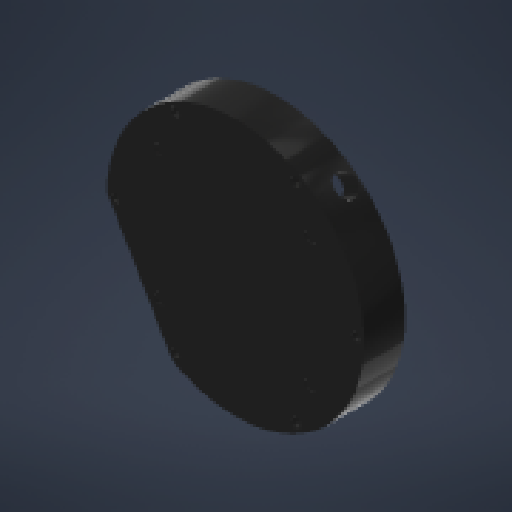
# Autodesk Inventor part: cover for electrical box
Saved by Autodesk Inventor 2027.1 (Build 311270010, 270A)
## iProperties
Created: 2026-10-20
Part Number: cover for electrical box
Material: Printed PLA Plastic
Document SubType Name: Modeling
Designer: youss
Density: 1.14 g/cm^3
Appearance: Smooth - Black
Author: youss
Autodesk Inventor part; units mm, degrees
ref_plane "XY Plane" through (0, 0, 0) normal (0, 0, 1) x (1, 0, 0)
sketch "Sketch1" plane through (0, 0, 0) normal (0, 0, 1) x (1, 0, 0)
  line L0 (-106.0871, 0) -> (113.3016, 0) projected
  line L1 (0, -109.7468) -> (0, 113.9116) projected
  circle A0 centre (0, 33) radius 2
  circle A1 centre (0, 0) radius 30
  circle A2 centre (28.5788, 16.5) radius 2
  circle A3 centre (28.5788, -16.5) radius 2
  circle A4 centre (0, -33) radius 2
  circle A5 centre (-28.5788, -16.5) radius 2
  circle A6 centre (-28.5788, 16.5) radius 2
  line L2 (-59.9972, 0.5821) -> (-29.4999, -52.2471)
  arc A7 (-29.4999, -52.2471) -> (-59.9972, 0.5821) centre (0, 0) ccw
  circle A8 centre (28, 48.4974) radius 2
  circle A9 centre (28, -48.4974) radius 2
  circle A10 centre (-28, 48.4974) radius 2
  circle A11 centre (56, 0) radius 2
  circle A12 centre (-52.9217, -3.6738) radius 2
  circle A13 centre (-32.5754, -38.9188) radius 2
  line L3 (-23.7061, -46.282) -> (-51.9341, 2.6162)
  arc A14 (-23.7061, -46.282) -> (-51.9341, 2.6162) centre (0, 0) ccw
  point P0 (0, 0)
  dimension "d5" = 8
  constraints: 15 centre point, 4 end point, 4 point on circle, 2 point on line, 1 other
  measures "d5" radial gap between concentric circles of A7 A14
extrude "Extrusion1" add sketch "Sketch1" along normal blind 17 contours L2 A7 L1 A14 L3 L0 | L0 L3 A14 L1 A7 L2 | A7 L0 A11 A14 L1 | L1 A14 L0 A11 A7
sketch "Sketch2" plane through (0, 0, 17) normal (0, 0, 1) x (1, 0, 0)
  line L0 (-59.9399, -2.6852) -> (-38.825, -45.7452) projected
  arc A0 (-38.825, -45.7452) -> (-59.9399, -2.6852) centre (0, 0) ccw projected
  circle A1 centre (-28, -48.4974) radius 2 projected
  circle A2 centre (-28, 48.4974) radius 2 projected
  circle A3 centre (-56, 0) radius 2 projected
  arc A4 (-32.404, -40.6692) -> (-51.9951, -0.7168) centre (0, 0) ccw projected
  line L1 (-32.404, -40.6692) -> (-51.9951, -0.7168) projected
  circle A5 centre (28, -48.4974) radius 2 projected
  circle A6 centre (28, 48.4974) radius 2 projected
  circle A7 centre (56, 0) radius 2 projected
extrude "Extrusion2" add sketch "Sketch2" along normal blind 2 contours A0 L0 | L1 A4
move faces "Move1" translate (0, 0, 26.75) faces at (-40.747, -34.3441, 17)
sketch "Sketch4" plane through (0, 0, 19) normal (0, 0, 1) x (1, 0, 0)
  line L0 (35, 30) -> (-35, 30)
  line L1 (-35, 30) -> (-35, -30)
  line L2 (-35, -30) -> (35, -30)
  line L3 (35, -30) -> (35, 30)
  line L4 (35, 30) -> (-35, -30)
  line L5 (35, -30) -> (-35, 30)
  arc A0 (-23.7061, -46.282) -> (-51.9341, 2.6162) centre (0, 0) ccw projected
  line L6 (-29.4999, -52.2471) -> (-59.9972, 0.5821) projected
  arc A1 (-29.4999, -52.2471) -> (-59.9972, 0.5821) centre (0, 0) ccw projected
  circle A2 centre (56, 0) radius 2 projected
  circle A3 centre (28, 48.4974) radius 2 projected
  circle A4 centre (28, -48.4974) radius 2 projected
  circle A5 centre (-56, 0) radius 2 projected
  circle A6 centre (-28, 48.4974) radius 2 projected
  circle A7 centre (-28, -48.4974) radius 2 projected
  circle A8 centre (35, 30) radius 2.5
  circle A9 centre (35, -30) radius 2.5
  circle A10 centre (-35, -30) radius 2.5
  circle A11 centre (-35, 30) radius 2.5
  dimension "d10" = 60
  dimension "d11" = 70
  dimension "d12" = 5
  dimension "d13" = 5
  dimension "d14" = 5
  dimension "d15" = 5
  constraints: 12 end point, 5 coincident, 4 centre point, 2 parallel, 1 horizontal, 1 midpoint, 1 perpendicular
  measures "d10" distance of L2.end L0.start
  measures "d11" distance of L1.end L2.end
  measures "d12" diameter of A8
  measures "d13" diameter of A9
  measures "d14" diameter of A10
  measures "d15" diameter of A11
extrude "Extrusion3" cut sketch "Sketch4" against normal blind 0.5 contours A11 L5 L0 | L0 L1 A11 | L5 A11 L1 | A8 L3 L0 | L0 L4 A8 | L3 A8 L4 | A10 L4 L1 | L1 L2 A10 | L4 A10 L2 | A9 L3 L5 | L5 L2 A9 | A9 L2 L3
sketch "Sketch5" plane through (-59.9972, 0.5821, 0) normal (-0.8660512, -0.4999554, 0) x (0, 0, 1)
  point P0 (0, -30.5)
sketch "Sketch6" plane through (-59.9972, 0.5821, 0) normal (-0.8660512, -0.4999554, 0) x (0, 0, 1)
  line L0 (0, -61) -> (19, -61) projected
  line L1 (0, 0) -> (0, -61) projected
  line L2 (0.56, -31.9394) -> (0.56, -25.5994)
  arc A0 (0.56, -31.9394) -> (1.86, -33.2394) centre (1.86, -31.9394) ccw
  arc A1 (1.86, -24.2994) -> (0.56, -25.5994) centre (1.86, -25.5994) ccw
  line L3 (2.42, -33.2394) -> (1.86, -33.2394)
  arc A2 (2.42, -33.2394) -> (3.72, -31.9394) centre (2.42, -31.9394) ccw
  line L4 (3.72, -25.5994) -> (3.72, -31.9394)
  arc A3 (3.72, -25.5994) -> (2.42, -24.2994) centre (2.42, -25.5994) ccw
  line L5 (1.86, -24.2994) -> (2.42, -24.2994)
  point P0 (0, -30.5)
  point P1 (2.14, -33.2394)
  point P2 (2.14, -33.2394)
  dimension "d18" = 27.7605
  dimension "d19" = 2.14
  constraints: 8 end point, 8 point on circle, 4 centre point, 1 midpoint
  measures "d18" distance from line of L0 point (2.14, -33.239)
  measures "d19" distance from line of L1 point (2.14, -33.239)
extrude "Extrusion4" cut sketch "Sketch6" against normal blind 61.63
chamfer "Chamfer1" distance 2 angle 45 8 edges at (-45.6137, -24.3338, 3.72) (-43.5693, -27.8753, 3.3392) (-43.3789, -28.205, 2.14) (-43.5693, -27.8753, 0.9408) (-45.6137, -24.3338, 0.56) (-47.6582, -20.7923, 0.9408) (-47.8485, -20.4625, 2.14) (-47.6582, -20.7923, 3.3392)
ref_plane "Work Plane1" through (-60, 0, 0) normal (1, 0, 0) x (0, 1, 0)
ref_plane "Work Plane2" through (0, 60, 0) normal (0, 1, 0) x (-1, 0, 0)
sketch "Sketch7" plane through (0, 60, 0) normal (0, 1, 0) x (-1, 0, 0)
  circle A0 centre (-7.2183, 7.2874) radius 4.95
  point P0 (0, 0)
  dimension "d25" = 9.9
  constraints: 1 centre point
  measures "d25" diameter of A0
extrude "Extrusion5" cut sketch "Sketch7" against normal blind 63
body "Solid1"
